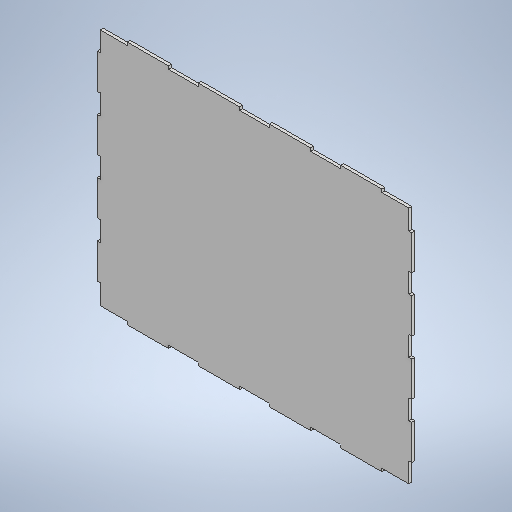
# Autodesk Inventor part: piso
Saved by Autodesk Inventor 2025.2 (Build 292293000, 293)
## iProperties
Created: 2025-05-19
Part Number: piso
Material: Generic
Document SubType Name: Modeling
Designer: laura
Density: 1 g/cm^3
Appearance: Default
Author: laura
Autodesk Inventor part; units mm, degrees
ref_plane "YZ Plane" through (0, 0, 0) normal (1, 0, 0) x (0, 1, 0)
ref_plane "XZ Plane" through (0, 0, 0) normal (0, 1, 0) x (-1, 0, 0)
ref_plane "XY Plane" through (0, 0, 0) normal (0, 0, 1) x (1, 0, 0)
sketch "Sketch1" plane through (0, 0, 0) normal (0, 0, 1) x (1, 0, 0)
  line L0 (-155, 120) -> (-155, -120)
  line L1 (-155, -120) -> (155, -120)
  line L2 (155, -120) -> (155, 120)
  line L3 (155, 120) -> (-155, 120)
  line L4 (-155, 0) -> (155, 0) construction
  point P0 (0, 0)
  point P1 (0, 0)
  dimension "d0" = 240
  dimension "d1" = 310
  constraints: 11 end point, 3 midpoint, 3 perpendicular, 1 coincident, 1 vertical
  measures "d0" distance between parallel lines of L1 L3
  measures "d1" distance of L0.end L1.end
extrude "Extrusion1" add sketch "Sketch1" along normal blind 3
sketch "Sketch2" plane through (0, 0, 3) normal (0, 0, 1) x (1, 0, 0)
  line L0 (155, 120) -> (-155, 120) projected
  line L1 (-128, 120) -> (-128, 123)
  line L2 (-128, 123) -> (-86.5, 123)
  line L3 (-86.5, 123) -> (-86.5, 120)
  line L4 (-56.5, 120) -> (-56.5, 123)
  line L5 (-56.5, 123) -> (-15, 123)
  line L6 (-15, 123) -> (-15, 120)
  line L7 (15, 120) -> (15, 123)
  line L8 (15, 123) -> (56.5, 123)
  line L9 (56.5, 123) -> (56.5, 120)
  line L10 (86.5, 120) -> (86.5, 123)
  line L11 (86.5, 123) -> (128, 123)
  line L12 (128, 123) -> (128, 120)
  line L13 (155, -120) -> (155, 120) projected
  line L14 (-155, 120) -> (-155, -120) projected
  line L15 (-155, 100) -> (-158, 100)
  line L16 (-158, 100) -> (-158, 65)
  line L17 (-158, 65) -> (-155, 65)
  line L18 (-155, -100) -> (-158, -100)
  line L19 (-158, -100) -> (-158, -65)
  line L20 (-158, -65) -> (-155, -65)
  line L21 (-155, -45) -> (-158, -45)
  line L22 (-158, -45) -> (-158, -10)
  line L23 (-158, -10) -> (-155, -10)
  line L24 (-155, 10) -> (-158, 10)
  line L25 (-158, 10) -> (-158, 45)
  line L26 (-158, 45) -> (-155, 45)
  line L27 (-155, -120) -> (155, -120) projected
  point P0 (0, 0)
  dimension "d4" = 27
  dimension "d5" = 30
  dimension "d6" = 30
  dimension "d7" = 30
  dimension "d8" = 27
  dimension "d9" = 3
  dimension "d10" = 20
  dimension "d11" = 20
  dimension "d12" = 20
  dimension "d13" = 20
  dimension "d14" = 20
  dimension "d15" = 3
  constraints: 48 end point, 10 point on line, 7 collinear, 7 vertical, 5 horizontal, 5 perpendicular, 1 parallel, 18 other
  measures "d4" distance between parallel lines of L13 L12
  measures "d5" distance between parallel lines of L10 L9
  measures "d6" distance between parallel lines of L7 L6
  measures "d7" distance between parallel lines of L4 L3
  measures "d11" distance between parallel lines of L26 L17
  measures "d12" distance between parallel lines of L23 L24
  measures "d13" distance between parallel lines of L20 L21
  measures "d14" distance between parallel lines of L27 L18
extrude "Extrusion2" add sketch "Sketch2" against normal blind 3 contours L0 L10 L11 L12 | L0 L7 L8 L9 | L0 L4 L5 L6 | L0 L1 L2 L3
extrude "Extrusion3" add sketch "Sketch2" against normal blind 3 contours L18 L19 L20 L14 | L21 L22 L23 L14 | L24 L25 L26 L14 | L17 L16 L15 L14
mirror "Mirror1" about plane through (0, 0, 0) normal (0, 1, 0) of "Extrusion2"
mirror "Mirror2" about plane through (0, 0, 0) normal (1, 0, 0) of "Extrusion3"
equation "\"d1\" = largo"
equation "\"largo\" = 310"
body "Solid1"
